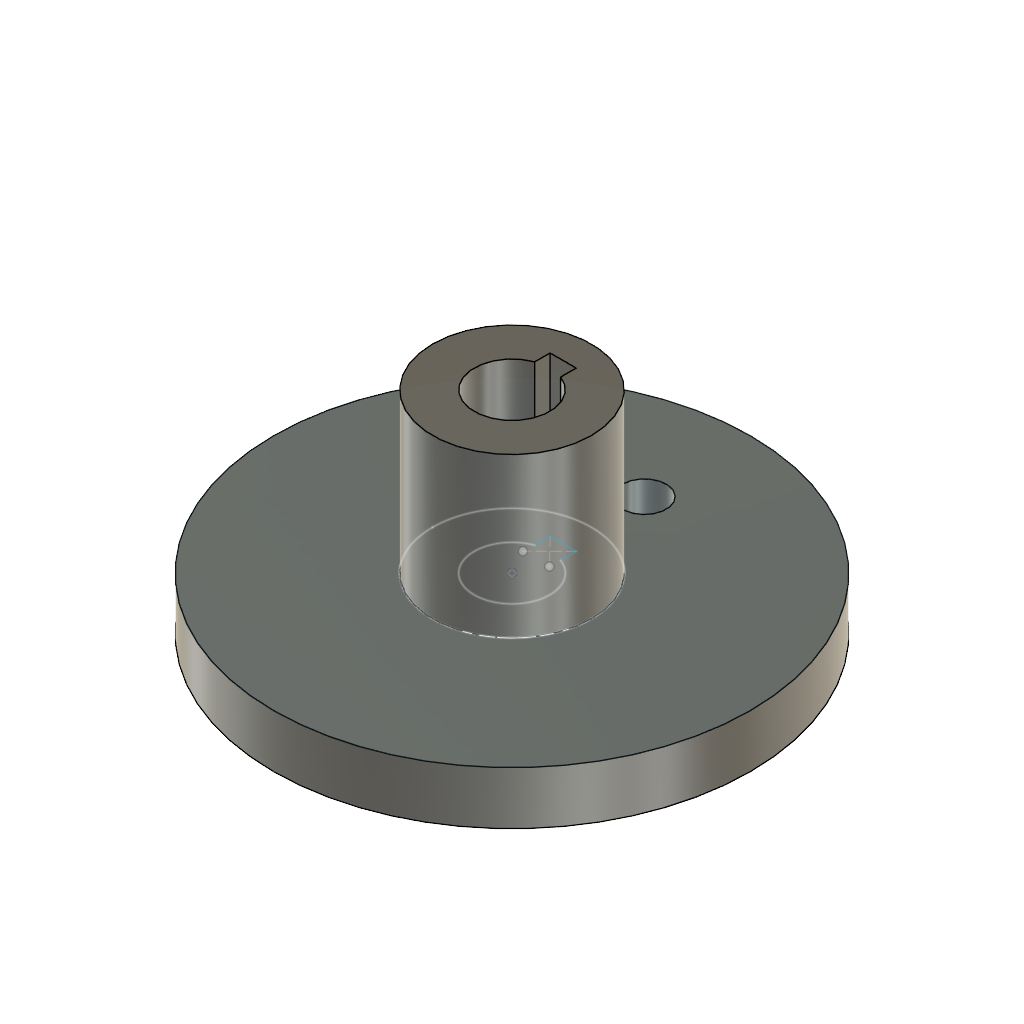
koncepcja-osiowo (Autodesk Fusion 360 archive; units mm, degrees)
design "KorbaV2RKO"
part number: 2026-10-06-00-30-41-262
Autodesk Fusion 360 part; units mm, degrees
sketch "Szkic1" plane through (0, 0, 0) normal (0, 0, 1) x (1, 0, 0)
  circle A0 centre (0, 0) radius 45
  circle A1 centre (0, 25) radius 4.125
  dimension "d1" = 90
  dimension "d2" = 8.25
  dimension "d3" = 25
  constraint coincident A0.centre origin
  measures "d1" diameter of A0
  measures "d2" diameter of A1
  measures "d3" distance of A0.centre A1.centre
extrude "Wyciągnięcie proste1" add sketch "Szkic1" along normal blind 10
sketch "Szkic2" plane through (0, 0, 10) normal (0, 0, 1) x (-1, 0, 0)
  circle A0 centre (0, -25) radius 4.125
  circle A1 centre (0, 0) radius 45
  circle A2 centre (0, 0) radius 15
  line L0 (-2.5181, -9.6074) -> (2.4162, -9.6074)
  line L1 (2.4162, -9.6074) -> (2.4162, -6.7028)
  line L2 (-2.5181, -6.6652) -> (-2.5181, -9.6074)
  line L3 (-2.5181, -9.6074) -> (2.5519, -4.6093) construction
  line L4 (2.4162, -9.6074) -> (-2.4481, -4.6097) construction
  arc A3 (2.4162, -6.7028) -> (-2.5181, -6.6652) centre (0, 0) ccw
  dimension "d6" = 14.25
  dimension "d7" = 30
  dimension "d10" = 5
  dimension "d11" = 5
  constraint coincident A1.centre A2.centre
  constraint concentric A2 A3
  constraint horizontal L0
  constraint perpendicular L0 L1
  constraint parallel L1 L2
  measures "d6" diameter of A3
  measures "d7" diameter of A2
  measures "d10" distance of L0.end L3.end
  measures "d11" distance of L3.end L4.end
extrude "Wyciągnięcie proste3" add sketch "Szkic2" along normal blind 30 contours A2
extrude "Wyciągnięcie proste2" [suppressed]

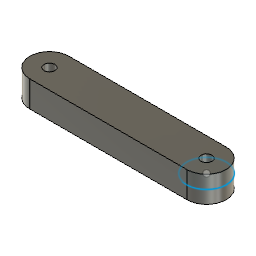
design "korbowodV1RKO"
part number: 2026-08-30-19-32-56-895
Autodesk Fusion 360 part; units mm, degrees
sketch "Szkic1" plane through (0, 0, 0) normal (0, 0, 1) x (1, 0, 0)
  line L0 (60, -15) -> (-60, -15)
  line L1 (-60, 15) -> (60, 15)
  line L2 (60, 4.125) -> (60, -4.125)
  line L3 (60, -15) -> (-60, 15) construction
  line L4 (-60, -15) -> (60, 15) construction
  circle A0 centre (-60, 0) radius 4.125
  circle A1 centre (-60, 0) radius 15
  circle A2 centre (60, 0) radius 4.125
  circle A3 centre (60, 0) radius 15
  dimension "d1" = 30
  dimension "d2" = 120
  dimension "d3" = 8.25
  dimension "d4" = 8.25
  constraint horizontal L0
  constraint parallel L0 L1
  constraint coincident L3 origin
  constraint coincident L4 origin
  constraint concentric A0 A1
  constraint coincident L0.end A1
  constraint concentric A2 A3
  constraint coincident L0.start A3
  constraint coincident A2 L2.end
  constraint coincident L2 A2.centre
  constraint coincident A2 L2.start
  measures "d1" distance of L0.start L1.end
  measures "d2" distance of L1.start L1.end
  measures "d3" diameter of A0
  measures "d4" diameter of A2
extrude "Wyciągnięcie proste1" add sketch "Szkic1" along normal blind 20
ref_plane "Płaszczyzna konstrukcyjna1" through (0, 0, 10) normal (0, 0, 1) x (1, 0, 0)
sketch "Szkic2" plane through (0, 0, 10) normal (0, 0, 1) x (1, 0, 0)
ref_plane "Płaszczyzna konstrukcyjna2" through (0, 0, 10) normal (0, 0, 1) x (1, 0, 0)
sketch "Szkic3" plane through (0, 0, 10) normal (0, 0, 1) x (1, 0, 0)
  circle A0 centre (60, 0) radius 15
  dimension "d12" = 30
  measures "d12" diameter of A0

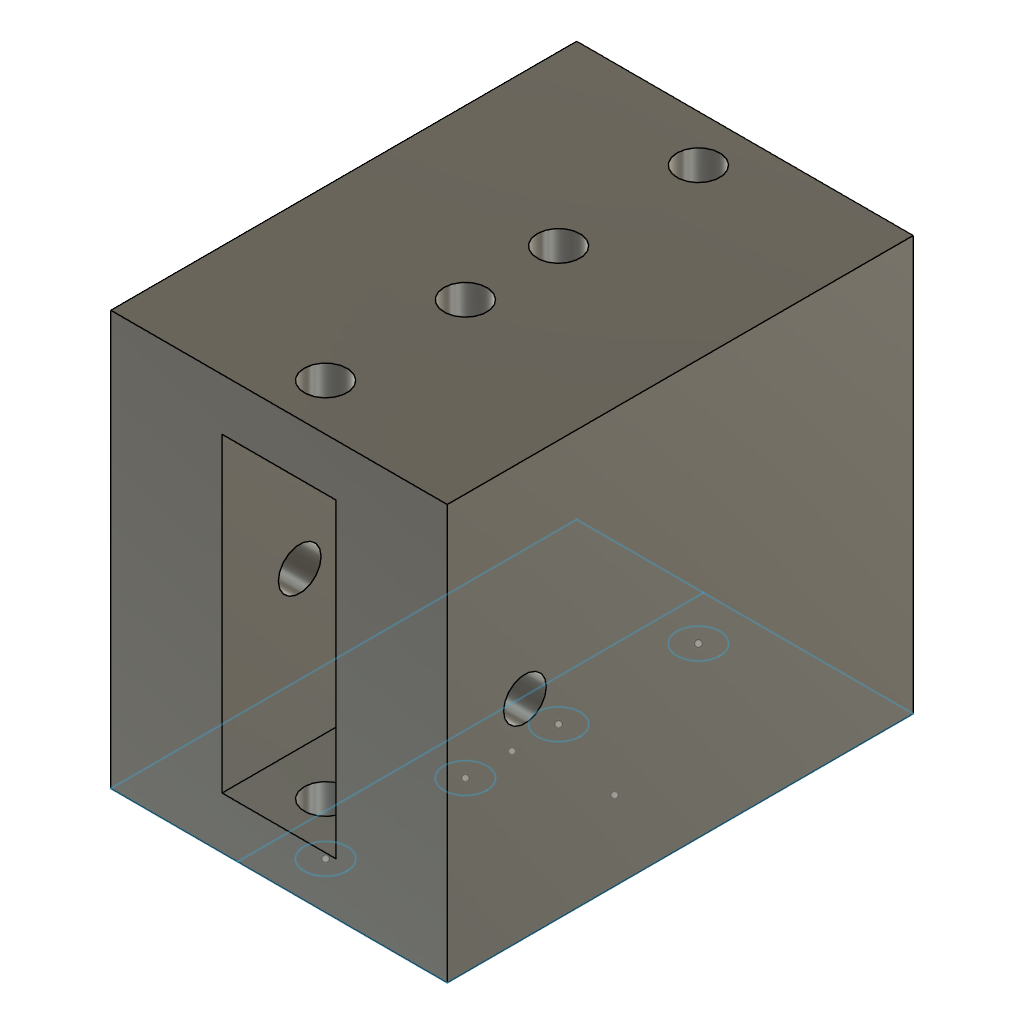
design "suwak-koncepcja osiowego polaczenia"
part number: 2026-10-18-23-51-32-050
Autodesk Fusion 360 part; units mm, degrees
sketch "Szkic1" plane through (0, 0, 0) normal (0, 0, 1) x (1, 0, 0)
  circle A0 centre (7.508, 6.4285) radius 4.1231
  circle A1 centre (7.508, 33.4285) radius 4.1231
  line L0 (-0.492, -47.5715) -> (-0.492, 42.4285)
  line L1 (40.008, 42.4285) -> (40.008, -47.5715)
  line L2 (-0.492, 42.4285) -> (40.008, 42.4285)
  line L3 (40.008, -47.5715) -> (-0.492, -47.5715)
  circle A2 centre (7.508, -11.5715) radius 4.1231
  circle A3 centre (7.508, -38.5715) radius 4.1231
  line L4 (-0.492, 42.4285) -> (-24.992, 42.4285)
  line L5 (-24.992, 42.4285) -> (-24.992, -47.5715)
  line L6 (-24.992, -47.5715) -> (-0.492, -47.5715)
  point P0 (24.7651, 0)
  point P1 (7.508, -2.5715)
  dimension "d5" = 0
  dimension "d6" = -27
  dimension "d7" = 90
  dimension "d12" = 0
  dimension "d13" = -72
  dimension "d20" = 0
  dimension "d21" = -45
  dimension "d24" = 40.5
  dimension "d26" = 9
  dimension "d27" = 24.5
  constraint horizontal L2
  constraint vertical L1
  constraint horizontal L3
  constraint vertical L0
  constraint perpendicular L0 L4
  constraint perpendicular L3 L5
  constraint perpendicular L0 L6
  measures "d7" distance of L1.start L1.end
  measures "d24" distance of L1.start L0.end
  measures "d26" distance of A1.centre L2
  measures "d27" distance of L0.end L4.end
extrude "Wyciągnięcie proste1" add sketch "Szkic1" along normal blind 80 contours L0 L1 L2 L3
extrude "Wyciągnięcie proste2" add sketch "Szkic1" along normal through all of body 1 contours L0 L4 L5 L6
sketch "Szkic2" plane through (0, 42.4285, 0) normal (0, 1, 0) x (-1, 0, 0)
  line L0 (-40.008, 0) -> (24.992, 0)
  line L1 (24.992, 0) -> (24.992, 80)
  line L2 (24.992, 80) -> (-40.008, 80)
  line L3 (-40.008, 80) -> (-40.008, 0)
  line L4 (-7.508, 80) -> (-7.508, 0) construction
  line L5 (-40.008, 40) -> (24.992, 40) construction
  line L6 (12.992, 65.5) -> (-28.008, 65.5)
  line L7 (-28.008, 65.5) -> (-28.008, 14.5)
  line L8 (-28.008, 14.5) -> (12.992, 14.5)
  line L9 (12.992, 14.5) -> (12.992, 65.5)
  line L10 (12.992, 65.5) -> (-28.008, 14.5) construction
  line L11 (-28.008, 65.5) -> (12.992, 14.5) construction
  point P0 (-7.508, 40)
  dimension "d29" = 51
  dimension "d30" = 41
  constraint coincident L2 L4.start
  constraint coincident L0 L4.end
  constraint perpendicular L0 L4
  constraint midpoint L3 L5.start
  constraint midpoint L1 L5.end
  constraint horizontal L6
  constraint perpendicular L6 L7
  constraint parallel L6 L8
  constraint parallel L7 L9
  constraint coincident L10 P0
  constraint coincident L11 P0
  constraint midpoint L5 P0
  measures "d29" distance of L6.end L7.end
  measures "d30" distance of L6.start L6.end
extrude "Wyciągnięcie proste3" cut sketch "Szkic2" against normal blind 42 contours L6 L7 L8 L9
sketch "Szkic3" plane through (0, -47.5715, 0) normal (0, -1, 0) x (1, 0, 0)
  line L0 (-24.992, 0) -> (40.008, 0)
  line L1 (40.008, 0) -> (40.008, 80)
  line L2 (40.008, 80) -> (-24.992, 80)
  line L3 (-24.992, 80) -> (-24.992, 0)
  line L4 (7.508, 80) -> (7.508, 0) construction
  line L5 (-24.992, 40) -> (40.008, 40) construction
  line L6 (18.508, 10) -> (-3.492, 10)
  line L7 (-3.492, 10) -> (-3.492, 70)
  line L8 (-3.492, 70) -> (18.508, 70)
  line L9 (18.508, 70) -> (18.508, 10)
  line L10 (18.508, 10) -> (-3.492, 70) construction
  line L11 (-3.492, 10) -> (18.508, 70) construction
  point P0 (7.508, 40)
  dimension "d33" = 22
  constraint midpoint L2 L4.start
  constraint midpoint L0 L4.end
  constraint symmetric L1 L3 L4
  constraint midpoint L3 L5.start
  constraint midpoint L1 L5.end
  constraint horizontal L6
  constraint perpendicular L6 L7
  constraint parallel L6 L8
  constraint parallel L7 L9
  constraint coincident L10 P0
  constraint coincident L11 P0
  constraint midpoint L4 P0
  measures "d33" distance of L7.end L8.end
extrude "Wyciągnięcie proste4" cut sketch "Szkic3" against normal blind 30 contours L6 L7 L8 L9
sketch "Szkic4" plane through (18.508, 0, 0) normal (-1, 0, 0) x (0, -1, 0)
  line L0 (47.5715, 10) -> (47.5715, 70)
  line L1 (47.5715, 70) -> (17.5715, 70)
  line L2 (17.5715, 70) -> (17.5715, 10)
  line L3 (17.5715, 10) -> (47.5715, 10)
  line L4 (32.5715, 70) -> (32.5715, 10) construction
  line L5 (17.5715, 40) -> (47.5715, 40) construction
  circle A0 centre (32.5715, 40) radius 4.125
  dimension "d36" = 8.25
  constraint midpoint L1 L4.start
  constraint midpoint L3 L4.end
  constraint midpoint L2 L5.start
  constraint midpoint L0 L5.end
  constraint midpoint L5 A0.centre
  measures "d36" diameter of A0
extrude "Wyciągnięcie proste5" cut sketch "Szkic4" along normal through all and the other way through all contours A0
